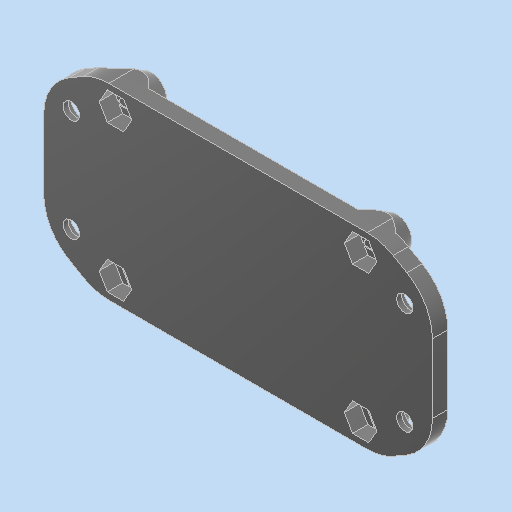
# Autodesk Inventor part: 3D_Feetech-controller-fix
Saved by Autodesk Inventor 2025.3 (Build 293356030, 356C)
## iProperties
Created: 2025-08-01
Part Number: 3D_Feetech-controller-fix
Material: 一般
Document SubType Name: Modeling
Designer: ibuki_ono
Density: 1 g/cm^3
Appearance: 滑らか - 黒
Author: ibuki_ono
## iProperties of the stored document 3D_Feetech-controller-fix_3D プリント.ipt
Created: 2025-08-01
Part Number: 3D_Feetech-controller-fix_3D プリント
Material: 一般
Document SubType Name: Modeling
Designer: ibuki_ono
Density: 1 g/cm^3
Appearance: 既定
Author: ibuki_ono
Autodesk Inventor part; units mm, degrees
ref_plane "YZ Plane" through (0, 0, 0) normal (1, 0, 0) x (0, 1, 0)
ref_plane "XZ Plane" through (0, 0, 0) normal (0, 1, 0) x (-1, 0, 0)
ref_plane "作業平面1" through (0, 0, 4) normal (0, 0, 1) x (1, 0, 0)
sketch "スケッチ1" plane through (0, 0, 4) normal (0, 0, 1) x (1, 0, 0)
  line L0 (25.9, 18.3) -> (-25.9, 18.3) projected
  line L1 (-25.9, -18.3) -> (25.9, -18.3) projected
  line L2 (-27.9, 16.3) -> (-27.9, -16.3) projected
  line L3 (27.9, -16.3) -> (27.9, 16.3) projected
  line L4 (-37.9, -12.5) -> (37.9, -12.5)
  line L5 (37.9, -12.5) -> (37.9, 12.5)
  line L6 (37.9, 12.5) -> (-37.9, 12.5)
  line L7 (-37.9, 12.5) -> (-37.9, -12.5)
  line L8 (-37.9, -12.5) -> (37.9, 12.5) construction
  line L9 (37.9, -12.5) -> (-37.9, 12.5) construction
  line L10 (-37.9, 12.5) -> (-27.9, 18.3)
  line L11 (-27.9, 18.3) -> (-25.9, 18.3)
  line L12 (25.9, 18.3) -> (27.9, 18.3)
  line L13 (27.9, 18.3) -> (37.9, 12.5)
  line L14 (37.9, -12.5) -> (27.9, -18.3)
  line L15 (27.9, -18.3) -> (25.9, -18.3)
  line L16 (-25.9, -18.3) -> (-27.9, -18.3)
  line L17 (-27.9, -18.3) -> (-37.9, -12.5)
  point P0 (0, 0)
  dimension "d1" = 25
  dimension "d2" = 10
  constraints: 28 end point, 5 parallel, 4 vertical alignment, 2 horizontal, 2 midpoint, 2 point on line, 1 perpendicular
  measures "d1" distance of L5.end L4.end
  measures "d2" distance between parallel lines of L7 L2
extrude "押し出し1" add sketch "スケッチ1" along normal blind 3
sketch "スケッチ2" plane through (0, 0, 4) normal (0, 0, -1) x (-1, 0, 0)
  line L0 (32.5, 10) -> (-32.5, 10) construction
  line L1 (-32.5, 10) -> (-32.5, -10) construction
  line L2 (-32.5, -10) -> (32.5, -10) construction
  line L3 (32.5, -10) -> (32.5, 10) construction
  line L4 (32.5, 10) -> (-32.5, -10) construction
  line L5 (-32.5, 10) -> (32.5, -10) construction
  point P0 (0, 0)
  dimension "d5" = 65
  dimension "d6" = 20
  constraints: 12 end point, 2 midpoint, 2 parallel, 1 horizontal, 1 perpendicular
  measures "d5" distance of L2.end L1.end
  measures "d6" distance of L1.end L0.end
hole "穴1" at (-32.5, -10, 4) at (-32.5, 10, 4) at (32.5, 10, 4) at (32.5, -10, 4) direction (0, 0, 1) diameter 3.2 end through all counterbore diameter 7 counterbore depth 2
sketch "スケッチ3" plane through (0, 0, 4) normal (0, 0, -1) x (-1, 0, 0)
  circle A0 centre (23.9, -14.3) radius 1.6 projected
  circle A1 centre (-23.9, -14.3) radius 1.6 projected
  circle A2 centre (-23.9, 14.3) radius 1.6 projected
  circle A3 centre (23.9, 14.3) radius 1.6 projected
  circle A4 centre (23.9, -14.3) radius 3
  circle A5 centre (23.9, 14.3) radius 3
  circle A6 centre (-23.9, -14.3) radius 3
  circle A7 centre (-23.9, 14.3) radius 3
  point P0 (0, 0)
  dimension "d14" = 6
  dimension "d15" = 6
  dimension "d16" = 6
  dimension "d17" = 6
  constraints: 4 centre point, 4 coincident
  measures "d14" diameter of A4
  measures "d15" diameter of A5
  measures "d16" diameter of A6
  measures "d17" diameter of A7
extrude "押し出し2" add sketch "スケッチ3" along normal blind 4 contours A0 | A1 | A2 | A3 | A4 | A5 | A6 | A7
sketch "スケッチ4" plane through (-23.9, -14.3, 0) normal (0, 0, -1) x (-1, 0, 0)
  circle A0 centre (0, 0) radius 3 projected
  circle A1 centre (0, 28.6) radius 3 projected
  circle A2 centre (-47.8, 0) radius 3 projected
  circle A3 centre (-47.8, 28.6) radius 3 projected
  point P0 (-23.9, 14.3)
hole "穴2" at (-23.9, -14.3, 0) at (-23.9, 14.3, 0) at (23.9, 14.3, 0) at (23.9, -14.3, 0) direction (0, 0, 1) diameter 3.2 end through all
chamfer "面取り1" distance 4 angle 30 1 edges at (-20.9, -14.3, 4) measured on face at (-20.9, -14.3, 3.5)
chamfer "面取り2" distance 4 angle 30 1 edges at (-20.9, 14.3, 4) measured on face at (-20.9, 14.3, 3.5)
chamfer "面取り3" distance 4 angle 30 1 edges at (26.9, -14.3, 4) measured on face at (26.9, -14.3, 3.5)
chamfer "面取り4" distance 4 angle 30 1 edges at (26.9, 14.3, 4) measured on face at (26.9, 14.3, 3.5)
sketch "スケッチ5" plane through (0, 0, 7) normal (0, 0, 1) x (1, 0, 0)
  circle A0 centre (-23.9, 14.3) radius 1.6 projected
  circle A1 centre (-23.9, 14.3) radius 3 projected
  line L0 (-20.7246, 14.3) -> (-22.3123, 11.55)
  line L1 (-22.3123, 11.55) -> (-25.4877, 11.55)
  line L2 (-25.4877, 11.55) -> (-27.0754, 14.3)
  line L3 (-27.0754, 14.3) -> (-25.4877, 17.05)
  line L4 (-25.4877, 17.05) -> (-22.3123, 17.05)
  line L5 (-22.3123, 17.05) -> (-20.7246, 14.3)
  point P0 (0, 0)
  dimension "d39" = 5.5
  constraints: 12 end point, 1 coincident, 1 horizontal alignment, 13 other
  measures "d39" distance between parallel lines of L1 L4
extrude "押し出し3" cut sketch "スケッチ5" against normal blind 3 contours A0 | A1 L0 L1 L2 L3 L4 L5 | A1 L5 L0 | A1 L4 L5 | L0 L1 A1 | A1 L3 L4 | L1 L2 A1 | A1 L2 L3
sketch "スケッチ6" plane through (0, 0, 4) normal (0, 0, 1) x (1, 0, 0)
  circle A0 centre (-23.9, 14.3) radius 1.6 projected
  line L0 (-25.4877, 17.05) -> (-22.3123, 17.05) projected
  line L1 (-27.0754, 14.3) -> (-25.4877, 17.05) projected
  line L2 (-25.4877, 11.55) -> (-27.0754, 14.3) projected
  line L3 (-22.3123, 11.55) -> (-25.4877, 11.55) projected
  line L4 (-20.7246, 14.3) -> (-22.3123, 11.55) projected
  line L5 (-22.3123, 17.05) -> (-20.7246, 14.3) projected
  line L6 (-26.1517, 12.7) -> (-21.6483, 12.7)
  line L7 (-21.3885, 13.15) -> (-23.6402, 17.05)
  line L8 (-25.4877, 17.05) -> (-22.3123, 17.05) projected
  line L9 (-24.1598, 17.05) -> (-26.4115, 13.15)
  line L10 (-27.0754, 14.3) -> (-25.4877, 17.05) projected
  line L11 (-22.3123, 17.05) -> (-20.7246, 14.3) projected
  line L12 (-22.3123, 11.55) -> (-25.4877, 11.55) projected
  circle A1 centre (-23.9, 14.3) radius 1.6 projected
  point P0 (0, 0)
  point P1 (-25.2856, 15.1)
  point P2 (-22.5144, 15.1)
  point P3 (-23.9, 12.7)
  constraints: 6 end point, 6 point on line, 3 parallel, 3 tangent
extrude "押し出し4" cut sketch "スケッチ6" against normal blind 0.2 contours A0 L7 L4 L6 | A0 L9 L0 L7 | L6 L2 L9 A0
mirror "ミラー1" about plane through (0, 0, 0) normal (1, 0, 0) of "押し出し3", "押し出し4"
mirror "ミラー2" about plane through (0, 0, 0) normal (0, 1, 0) of "押し出し3", "押し出し4", "ミラー1"
sketch "スケッチ7" plane through (0, 0, 4) normal (0, 0, -1) x (-1, 0, 0)
  line L0 (27.5, 7.3) -> (-27.5, 7.3)
  line L1 (-27.5, 7.3) -> (-27.5, -7.3)
  line L2 (-27.5, -7.3) -> (27.5, -7.3)
  line L3 (27.5, -7.3) -> (27.5, 7.3)
  line L4 (27.5, 7.3) -> (-27.5, -7.3) construction
  line L5 (-27.5, 7.3) -> (27.5, -7.3) construction
  line L6 (16.9, 15.3) -> (-16.9, 15.3)
  line L7 (-16.9, 15.3) -> (-16.9, -15.3)
  line L8 (-16.9, -15.3) -> (16.9, -15.3)
  line L9 (16.9, -15.3) -> (16.9, 15.3)
  line L10 (16.9, 15.3) -> (-16.9, -15.3) construction
  line L11 (-16.9, 15.3) -> (16.9, -15.3) construction
  line L12 (20.4086, -18.3) -> (-20.4086, -18.3) projected
  circle A0 centre (23.9, -14.3) radius 1.6 projected
  circle A1 centre (32.5, -10) radius 1.6 projected
  point P0 (0, 0)
  point P1 (16.9, 7.3)
  point P2 (-16.9, 7.3)
  point P3 (-16.9, -7.3)
  point P4 (16.9, -7.3)
  dimension "d44" = 3
  dimension "d45" = 7
  dimension "d46" = 7
  dimension "d47" = 5
  constraints: 24 end point, 4 midpoint, 4 parallel, 2 horizontal, 2 perpendicular
  measures "d44" distance between parallel lines of L8 L12
  measures "d45" distance from line of A0.centre L9
  measures "d46" distance from line of A0.centre L2
  measures "d47" distance from line of A1.centre L3
extrude "押し出し5" cut sketch "スケッチ7" against normal blind 2 contours L3 L2 L9 L0 | L9 L2 L7 L0 | L0 L7 L6 L9 | L7 L2 L1 L0 | L9 L8 L7 L2
fillet "フィレット1" radius 5 12 edges at (-16.9, -7.3, 5) (-27.5, -7.3, 5) (-27.5, 7.3, 5) (-16.9, 7.3, 5) (-16.9, 15.3, 5) (-16.9, -15.3, 5) (16.9, -15.3, 5) (16.9, -7.3, 5) (27.5, -7.3, 5) (27.5, 7.3, 5) (16.9, 7.3, 5) (16.9, 15.3, 5)
chamfer "面取り5" distance 2 angle 45 20 edges at (-0.101, -15.3, 6) (15.0623, -14.173, 6) (18.5357, -8.427, 6) (22.099, -7.3, 6) (26.0355, -5.8355, 6) (27.5, 0, 6) (26.0355, 5.8355, 6) (22.2, 7.3, 6) (18.7377, 8.427, 6) (15.2643, 14.173, 6) (0, 15.3, 6) (-15.2643, 14.173, 6) (-18.7377, 8.427, 6) (-22.2, 7.3, 6) (-26.0355, 5.8355, 6) (-27.5, 0, 6) (-26.0355, -5.8355, 6) (-22.2, -7.3, 6) (-18.7377, -8.427, 6) (-15.2643, -14.173, 6)
fillet "フィレット2" radius 10 8 edges at (-37.9, 12.5, 5.5) (-37.9, -12.5, 5.5) (-27.9, 18.3, 5.5) (-27.9, -18.3, 5.5) (27.9, 18.3, 5.5) (37.9, 12.5, 5.5) (37.9, -12.5, 5.5) (27.9, -18.3, 5.5)
equation "\"d46\" = d45"
